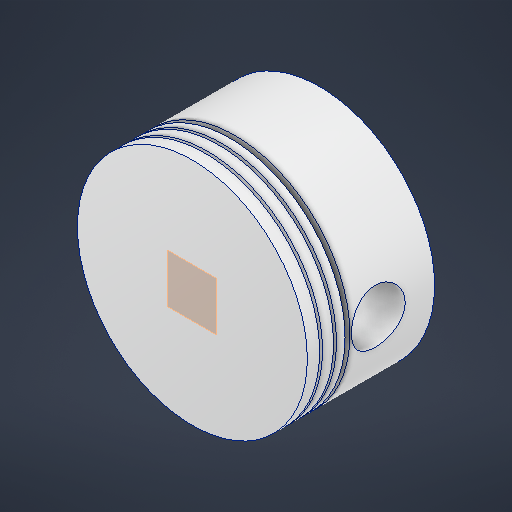
# Autodesk Inventor part: Piston
Saved by Autodesk Inventor 2027.1 (Build 311270010, 270A)
## iProperties
Created: 2026-10-17
Part Number: Piston
Material: Aluminum 6061
Document SubType Name: Modeling
Designer: kashyap
Density: 2.7 g/cm^3
Appearance: Aluminum - Flat
Mass: 455.669 g
Surface Area: 530.297 cm^2
Volume: 168.766 cm^3
Material_Status: Assumed for this reconstruction
Author: kashyap
Autodesk Inventor part; units mm, degrees
derived "V6_Engine_Master.ipt"
ref_plane "Crown_Plane" through (0, 0, 29) normal (0, 0, 1) x (1, 0, 0)
ref_plane "Skirt_Bottom_Plane" through (0, 0, -23) normal (0, 0, 1) x (1, 0, 0)
ref_plane "Pin_Mid_Plane" through (0, 0, 0) normal (1, 0, 0) x (0, 1, 0)
sketch "SK_Body" plane through (0, 0, -23) normal (0, 0, 1) x (1, 0, 0)
  circle A0 centre (0, 0) radius 46.985
  dimension "d22" = 93.97
  constraints: 1 centre point
  measures "d22" diameter of A0
extrude "Piston_Body" add sketch "SK_Body" along normal blind 52
sketch "SK_Cavity" plane through (0, 0, -23) normal (0, 0, 1) x (1, 0, 0)
  circle A0 centre (0, 0) radius 40
  dimension "d25" = 80
  constraints: 1 centre point
  measures "d25" diameter of A0
extrude "Underside_Cavity" cut sketch "SK_Cavity" along normal blind 44
ref_plane "Pin_Boss_Plane_Front" through (-12, 0, 0) normal (1, 0, 0) x (0, 1, 0)
sketch "SK_Pin_Boss_Front" plane through (-12, 0, 0) normal (1, 0, 0) x (0, 1, 0)
  line L0 (0, 28.4005) -> (0, -23.403) construction
  line L1 (-21, 0) -> (21, 0) construction
  line L2 (-15, -16.0025) -> (15, -16.0025)
  line L3 (15, -16.0025) -> (15, 21)
  line L4 (15, 21) -> (-15, 21)
  line L5 (-15, 21) -> (-15, -16.0025)
  dimension "d29" = 15
  dimension "d30" = 15
  dimension "d31" = 16.0025
  dimension "d32" = 21
  constraints: 8 end point, 2 parallel, 1 horizontal, 1 perpendicular
  measures "d29" distance between parallel lines of L5 L0
  measures "d30" distance between parallel lines of L3 L0
  measures "d31" distance between parallel lines of L2 L1
  measures "d32" distance between parallel lines of L4 L1
extrude "Pin_Boss_Front" add sketch "SK_Pin_Boss_Front" against normal blind 29
ref_plane "Pin_Boss_Plane_Rear" through (12, 0, 0) normal (1, 0, 0) x (0, 1, 0)
sketch "SK_Pin_Boss_Rear" plane through (12, 0, 0) normal (1, 0, 0) x (0, 1, 0)
  line L0 (0, 28.4005) -> (0, -23.403) construction
  line L1 (-21, 0) -> (21, 0) construction
  line L2 (-15, -16.0025) -> (15, -16.0025)
  line L3 (15, -16.0025) -> (15, 21)
  line L4 (15, 21) -> (-15, 21)
  line L5 (-15, 21) -> (-15, -16.0025)
  dimension "d36" = 15
  dimension "d37" = 15
  dimension "d38" = 16.0025
  dimension "d39" = 21
  constraints: 8 end point, 2 parallel, 1 horizontal, 1 perpendicular
  measures "d36" distance between parallel lines of L5 L0
  measures "d37" distance between parallel lines of L3 L0
  measures "d38" distance between parallel lines of L2 L1
  measures "d39" distance between parallel lines of L4 L1
extrude "Pin_Boss_Rear" add sketch "SK_Pin_Boss_Rear" along normal blind 29
sketch "SK_Pin_Bore" plane through (0, 0, 0) normal (1, 0, 0) x (0, 1, 0)
  circle A0 centre (0, 0) radius 11.0025
  dimension "d42" = 22.005
  constraints: 1 centre point
  measures "d42" diameter of A0
extrude "Pin_Bore" cut sketch "SK_Pin_Bore" along normal mid plane 95.97
ref_plane "Ring_1_Top_Plane" through (0, 0, 24) normal (0, 0, 1) x (1, 0, 0)
sketch "SK_Ring_1_Groove" plane through (0, 0, 24) normal (0, 0, 1) x (1, 0, 0)
  circle A0 centre (0, 0) radius 47.985
  circle A1 centre (0, 0) radius 43.485
  dimension "d46" = 95.97
  dimension "d47" = 86.97
  constraints: 2 centre point
  measures "d46" diameter of A0
  measures "d47" diameter of A1
extrude "Ring_1_Groove" cut sketch "SK_Ring_1_Groove" against normal blind 1.2
ref_plane "Ring_2_Top_Plane" through (0, 0, 18.3) normal (0, 0, 1) x (1, 0, 0)
sketch "SK_Ring_2_Groove" plane through (0, 0, 18.3) normal (0, 0, 1) x (1, 0, 0)
  circle A0 centre (0, 0) radius 47.985
  circle A1 centre (0, 0) radius 43.485
  dimension "d51" = 95.97
  dimension "d52" = 86.97
  constraints: 2 centre point
  measures "d51" diameter of A0
  measures "d52" diameter of A1
extrude "Ring_2_Groove" cut sketch "SK_Ring_2_Groove" against normal blind 1.2
ref_plane "Oil_Ring_Top_Plane" through (0, 0, 13.6) normal (0, 0, 1) x (1, 0, 0)
sketch "SK_Oil_Ring_Groove" plane through (0, 0, 13.6) normal (0, 0, 1) x (1, 0, 0)
  circle A0 centre (0, 0) radius 47.985
  circle A1 centre (0, 0) radius 43.485
  dimension "d56" = 95.97
  dimension "d57" = 86.97
  constraints: 2 centre point
  measures "d56" diameter of A0
  measures "d57" diameter of A1
extrude "Oil_Ring_Groove" cut sketch "SK_Oil_Ring_Groove" against normal blind 2
equation "\"d22\" = Piston_Diameter"
equation "\"d23\" = Piston_Total_Length"
equation "\"d25\" = Piston_Inner_Dia"
equation "\"d26\" = Piston_Total_Length - Piston_Crown_Thickness"
equation "\"d29\" = 0.5 * Pin_Boss_Width"
equation "\"d30\" = 0.5 * Pin_Boss_Width"
equation "\"d32\" = Compression_Height - Piston_Crown_Thickness"
equation "\"d36\" = 0.5 * Pin_Boss_Width"
equation "\"d37\" = 0.5 * Pin_Boss_Width"
equation "\"d39\" = Compression_Height - Piston_Crown_Thickness"
equation "\"d42\" = Pin_Hole_Diameter"
equation "\"d47\" = Piston_Diameter - 2 * Ring_Groove_Depth"
equation "\"d48\" = Ring_1_Groove_Width"
equation "\"d52\" = Piston_Diameter - 2 * Ring_Groove_Depth"
equation "\"d53\" = Ring_2_Groove_Width"
equation "\"d57\" = Piston_Diameter - 2 * Ring_Groove_Depth"
equation "\"d58\" = Oil_Ring_Groove_Width"
equation "\"Piston_Diameter\" = 93.97"
equation "\"Piston_Total_Length\" = 52"
equation "\"Piston_Inner_Dia\" = 80"
equation "\"Piston_Crown_Thickness\" = 8"
equation "\"Pin_Boss_Width\" = 30"
equation "\"Compression_Height\" = 29"
equation "\"Pin_Hole_Diameter\" = 22.005"
equation "\"Ring_Groove_Depth\" = 3.5"
equation "\"Ring_1_Groove_Width\" = 1.2"
equation "\"Ring_2_Groove_Width\" = 1.2"
equation "\"Oil_Ring_Groove_Width\" = 2"
body "Solid1"
